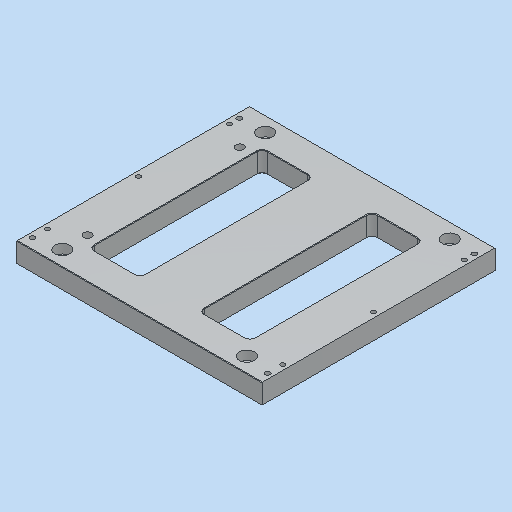
# Autodesk Inventor part: MM0948AN130_G01_115
Saved by Autodesk Inventor 2023.3 (Build 273359000, 359)
## iProperties
Part Number: MM0948AN130_G01_115
Material: 3.3547 AlMg4,5Mn0,7 - AW 5083
Description: =<RBPARTNOTITLE2>
Document SubType Name: Modeling
Designer: ric7an
Mass: 2067.87 g
Surface Area: 1195.22 cm^2
Volume: 765.876 cm^3
Density: 2.7 g/cm^3
Appearance: Aluminium AnP
Created: 2023-03-23
RBDOCUMENTTYPE: DRF
RBDOCUMENTVERSION: 00
RBDRAWINGMAINSCALE: 1:1
RBDRAWINGMISSINGSPEC: --
RBDRAWINGVOLUME: --
RBGBEDGESIN1: +0,5
RBGBEDGESIN2: +0,2
RBGBEDGESOUT1: -0,3
RBGBEDGESOUT2: -0,1
RBMATERIAL: =<Material>
RBMATMEETS: --
RBMATNO: =<Part Number>
RBPARTMADEOF: 20 x 231 x 243 (FM)
RBPARTNO: SIEHE MNR
RBPARTNOTITLE1: manufactured part
RBPARTNOTITLE2: Anfertigungsteil
RBPARTSAFETYINDICATOR: --
RBSURFACE: anodised colourless
RBSURFACE2: eloxiert farblos
RBZEDGESNORM: ISO13715:2002-06
RBZGENDIMCLASS: m
RBZGENDIMNORM: ISO 2768-1:1989-11
RBZGENGEOCLASS: H
RBZGENGEONORM: ISO 2768-2:1989-11
RBZSURFACENORM: ISO13D2:2002-02
RBZTOLERANCENORM: ISO 14405-1:2010-12
AnP_Material: =<Material>
AnP_TemplVers: 20190222
AnP_Kategorie: 1
MaxAbmaße: 20 x 231 x 243 (FM)
AnP_Kommentar_aktuell: =<Comments>
AnP_Material_aktuell: =<Material>
Author: FH/Wi
Keywords: =<RBPARTMADEOF>
Comments: =<RBSURFACE2>
Revision Number: 01
Autodesk Inventor part; units mm, degrees
ref_plane "YZ Plane" through (0, 0, 0) normal (1, 0, 0) x (0, 1, 0)
ref_plane "XZ Plane" through (0, 0, 0) normal (0, 1, 0) x (-1, 0, 0)
ref_plane "XY Plane" through (0, 0, 0) normal (0, 0, 1) x (1, 0, 0)
sketch "Skizze1" plane through (0, 0, 0) normal (0, 0, 1) x (1, 0, 0)
  line L0 (-121.5, 231) -> (121.5, 231)
  line L1 (121.5, 231) -> (121.5, 0)
  line L2 (121.5, 0) -> (-121.5, 0)
  line L3 (-121.5, 0) -> (-121.5, 231)
  line L4 (0, 277.2) -> (0, -46.2) projected
  line L5 (-170.1, 0) -> (170.1, 0) projected
  point P0 (0, 0)
  dimension "d0" = 243
  dimension "d1" = 231
  constraints: 8 end point, 2 parallel, 1 collinear, 1 horizontal, 1 perpendicular, 1 other
  measures "d0" distance of L0.start L0.end
  measures "d1" distance of L0.end L1.end
extrude "Extrusion1" add sketch "Skizze1" along normal blind 20
sketch "Skizze18" plane through (0, 0, 20) normal (0, 0, -1) x (-1, 0, 0)
  line L0 (-91.5, 216) -> (91.5, 216)
  line L1 (91.5, 216) -> (91.5, 15)
  line L2 (91.5, 15) -> (-91.5, 15)
  line L3 (-91.5, 15) -> (-91.5, 216)
  line L4 (121.5, 231) -> (-121.5, 231) projected
  line L5 (-121.5, 231) -> (-121.5, 0) projected
  point P0 (0, 0)
  point P1 (0, 231)
  point P2 (0, 216)
  point P3 (-121.5, 115.5)
  point P4 (-91.5, 115.5)
  dimension "d134" = 15
  dimension "d135" = 30
  constraints: 8 end point, 4 midpoint, 2 coincident, 2 parallel, 1 horizontal, 1 horizontal alignment, 1 perpendicular, 1 vertical alignment
  measures "d134" distance between parallel lines of L0 L4
  measures "d135" distance between parallel lines of L3 L5
hole "Bohrung6" at (91.5, 15, 20) at (91.5, 216, 20) at (-91.5, 216, 20) at (-91.5, 15, 20) direction (0, 0, -1) diameter 9 end through all counterbore diameter 15 counterbore depth 9 clearance for "Inbusschraube ISO 4762  versenkt" size "M8" standard "ISO"
sketch "Skizze19" plane through (0, 0, 0) normal (0, 0, -1) x (-1, 0, 0)
  circle A0 centre (91.5, 216) radius 4.5 projected
  circle A1 centre (-91.5, 15) radius 4.5 projected
  circle A2 centre (91.5, 15) radius 4.5 projected
  point P0 (0, 0)
  point P1 (91.5, 40)
  point P2 (91.5, 191)
  dimension "d143" = 25
  dimension "d145" = 25
  constraints: 2 vertical alignment
  measures "d143" distance of point (91.5, 191) A0.centre
  measures "d145" distance of A2.centre point (91.5, 40)
hole "Bohrung7" at (-91.5, 40, 0) at (-91.5, 191, 0) direction (0, 0, 1) diameter 8 end through all
sketch "Skizze10" plane through (0, 0, 20) normal (0, 0, 1) x (1, 0, 0)
  line L0 (0, 331.2) -> (0, -55.2) projected
  line L1 (-79.5, 201) -> (-29.5, 201)
  line L2 (-29.5, 201) -> (-29.5, 30)
  line L3 (-29.5, 30) -> (-79.5, 30)
  line L4 (-79.5, 30) -> (-79.5, 201)
  line L5 (29.5, 201) -> (79.5, 201)
  line L6 (79.5, 201) -> (79.5, 30)
  line L7 (79.5, 30) -> (29.5, 30)
  line L8 (29.5, 30) -> (29.5, 201)
  line L9 (121.5, 231) -> (-121.5, 231) projected
  line L10 (-81.5, 231) -> (-53.5, 231) construction
  line L11 (-53.5, 231) -> (-53.5, 223) construction
  line L12 (-53.5, 223) -> (-81.5, 223) construction
  line L13 (-81.5, 223) -> (-81.5, 231) construction
  line L14 (-67.5, 231) -> (-67.5, 223) construction
  circle A0 centre (-91.5, 216) radius 4.5 projected
  line L15 (-121.5, 231) -> (-121.5, 0) projected
  point P0 (-103.502, 254.8851)
  point P1 (-121.5, 115.5)
  point P2 (-79.5, 115.5)
  dimension "d88" = 30
  dimension "d89" = 50
  dimension "d150" = 8
  dimension "d151" = 28
  dimension "d153" = 67.5
  dimension "d155" = 12
  constraints: 26 end point, 6 parallel, 4 midpoint, 3 horizontal, 3 perpendicular, 2 point on line, 1 collinear, 1 horizontal alignment, 2 other
  measures "d88" distance between parallel lines of L9 L1
  measures "d89" distance of L1.start L1.end
  measures "d150" distance of L10.end L11.end
  measures "d151" distance of L10.start L10.end
  measures "d153" distance between parallel lines of L0 L14
  measures "d155" distance from line of L4 A0.centre
extrude "Extrusion10" cut sketch "Skizze10" against normal through all contours L1 L2 L3 L4 | L5 L6 L7 L8
fillet "Rundung7" radius 5 8 edges at (-79.5, 201, 10) (-29.5, 201, 10) (-29.5, 30, 10) (-79.5, 30, 10) (29.5, 201, 10) (79.5, 201, 10) (29.5, 30, 10) (79.5, 30, 10)
sketch "Skizze14" plane through (0, 0, 0) normal (0, 0, -1) x (-1, 0, 0)
  line L0 (0, -47.6) -> (0, 285.6) projected
  line L1 (-170.1, 0) -> (170.1, 0) projected
  line L2 (121.5, 231) -> (-121.5, 231) projected
  line L3 (-121.5, 231) -> (-121.5, 0) projected
  line L4 (-116.5, 205.5) -> (116.5, 205.5)
  line L5 (116.5, 205.5) -> (116.5, 25.5)
  line L6 (116.5, 25.5) -> (-116.5, 25.5)
  line L7 (-116.5, 25.5) -> (-116.5, 205.5)
  point P0 (0, 0)
  point P1 (-116.5, 115.5)
  point P2 (116.5, 115.5)
  dimension "d78" = 180
  dimension "d79" = 25.5
  dimension "d107" = 231
  dimension "d149" = 5
  constraints: 8 end point, 2 midpoint, 2 parallel, 2 symmetric about line, 1 horizontal, 1 perpendicular, 1 vertical alignment
  measures "d78" distance of point (-116.5, 25.5) L4.start
  measures "d79" distance from line of L1 point (-116.5, 25.5)
  measures "d107" distance between parallel lines of L1 L2
  measures "d149" distance from line of point (-116.5, 25.5) L3
hole "Bohrung3" at (116.5, 205.5, 0) at (116.5, 25.5, 0) at (-116.5, 205.5, 0) at (-116.5, 25.5, 0) at (116.5, 115.5, 0) at (-116.5, 115.5, 0) direction (0, 0, 1) diameter 4.5 end through all counterbore diameter 8 counterbore depth 4.6 clearance for "Inbusschraube ISO 4762  versenkt" size "M4" standard "ISO"
chamfer "Fase1" distance 0.5 angle 45 38 edges at (-79.5, 115.5, 20) (-78.0355, 199.5355, 20) (-54.5, 201, 20) (-30.9645, 199.5355, 20) (-29.5, 115.5, 20) (-30.9645, 31.4645, 20) (-54.5, 30, 20) (-78.0355, 31.4645, 20) (-79.5, 115.5, 0) (-78.0355, 31.4645, 0) (-54.5, 30, 0) (-30.9645, 31.4645, 0) (-29.5, 115.5, 0) (-30.9645, 199.5355, 0) (-54.5, 201, 0) (-78.0355, 199.5355, 0) (29.5, 115.5, 20) (30.9645, 199.5355, 20) (54.5, 201, 20) (78.0355, 199.5355, 20) (79.5, 115.5, 20) (78.0355, 31.4645, 20) (54.5, 30, 20) (30.9645, 31.4645, 20) (29.5, 115.5, 0) (30.9645, 31.4645, 0) (54.5, 30, 0) (78.0355, 31.4645, 0) (79.5, 115.5, 0) (78.0355, 199.5355, 0) (54.5, 201, 0) (30.9645, 199.5355, 0) (0, 0, 20) (121.5, 115.5, 0) (0, 0, 0) (-121.5, 115.5, 0) (0, 231, 0) (0, 231, 20)
sketch "Skizze16" plane through (0, 0, 20) normal (0, 0, 1) x (1, 0, 0)
  circle A0 centre (-116.5, 25.5) radius 2.25 projected
  circle A1 centre (116.5, 25.5) radius 2.25 projected
  circle A2 centre (116.5, 205.5) radius 2.25 projected
  point P0 (-116.5, 215.5)
  point P1 (-116.5, 10.5)
  point P2 (116.5, 215.5)
  point P3 (116.5, 10.5)
  dimension "d148" = 15
  dimension "d154" = 10
  constraints: 4 vertical alignment, 2 horizontal alignment
  measures "d148" distance of point (116.5, 10.5) A1.centre
  measures "d154" distance of A2.centre point (116.5, 215.5)
hole "Bohrung4" at (-116.5, 215.5, 20) at (-116.5, 10.5, 20) at (116.5, 215.5, 20) at (116.5, 10.5, 20) direction (0, 0, -1) diameter 5 depth 15 tip angle 118
equation "\"d79\" = -0.5 * d78 + 0.5 * d107"
